Autodesk Fusion 360 part; units mm, degrees
(part 3 of 3)
equation "d216 = alignh_diameter_Ref"
equation "d217 = alignh_diameter_Ref"
equation "d218 = alignh_diameter_Ref"
equation "d219 = alignh_diameter_Ref"
equation "d224 = alignh_diameter_Ref"
equation "d226 = alignh_height_Ref"
equation "d229 = alignh_diameter_Ref * 0.5"
equation "d232 = sw_size_Ref * 0.5"
equation "d233 = sw_size_Ref * 1.5"
equation "d234 = sw_size_Ref * 1.5 + plt_border_width_Ref"
equation "d235 = sw_size_Ref * 1.5"
equation "d239 = case_top_inner_border_side_fillet_Ref"
equation "d243 = case_top_inner_border_top_fillet_Ref"
equation "pcb_clearance_Ref = 8.5 mm"
equation "case_bot_min_thickness_Ref = 3 mm"
equation "case_max_length_Ref = max(7 * sw_size_Ref + plt_border_width_Ref * 2 + case_border_width_Ref * 2; 8 * sw_size_Ref + ( plt_border_width_Ref + case_border_width_Ref ) * 2 + 7.885 mm)"
equation "case_bot_angle_Ref = 2.75 deg"
equation "case_bot_max_thickness_Ref = case_max_length_Ref / tan(90 deg - case_bot_angle_Ref) + case_bot_min_thickness_Ref"
equation "d250 = alignh_diameter_Ref"
equation "d254 = alignh_diameter_Ref"
equation "d255 = alignh_diameter_Ref"
equation "ctrl_socket_height_Ref = 4.191 mm"
equation "bat_wall_thickness_Ref = 2.5 mm"
equation "bat_offset_Ref = 25 mm + bat_wall_thickness_Ref + bat_length_Ref * 0.5"
equation "sw_hotswap_clearance_Ref = 1.9 mm"
equation "d262 = alignh_diameter_Ref"
equation "case_side_fillet_Ref = 2.5 mm"
equation "case_top_fillet_Ref = 0.5 mm"
equation "d266 = case_side_fillet_Ref"
equation "d270 = case_top_fillet_Ref"
equation "case_top_inner_border_side_fillet_Ref = 1.5 mm"
equation "case_top_inner_border_top_fillet_Ref = 1 mm"
equation "usbc_contour_height_Ref = 4.5 mm"
equation "usbc_contour_length_Ref = 12 mm"
equation "assemblyscr_head_diameter_Ref = 4.15 mm"
equation "assemblyscr_head_width_Ref = 0.85 mm"
equation "rf_diameter_Ref = 10 mm"
equation "rf_width_Ref = 0.5 mm"
equation "rf_voffset_Ref = case_border_width_Ref + 10 mm"
equation "rf_hoffset_Ref = case_border_width_Ref + 15 mm"
